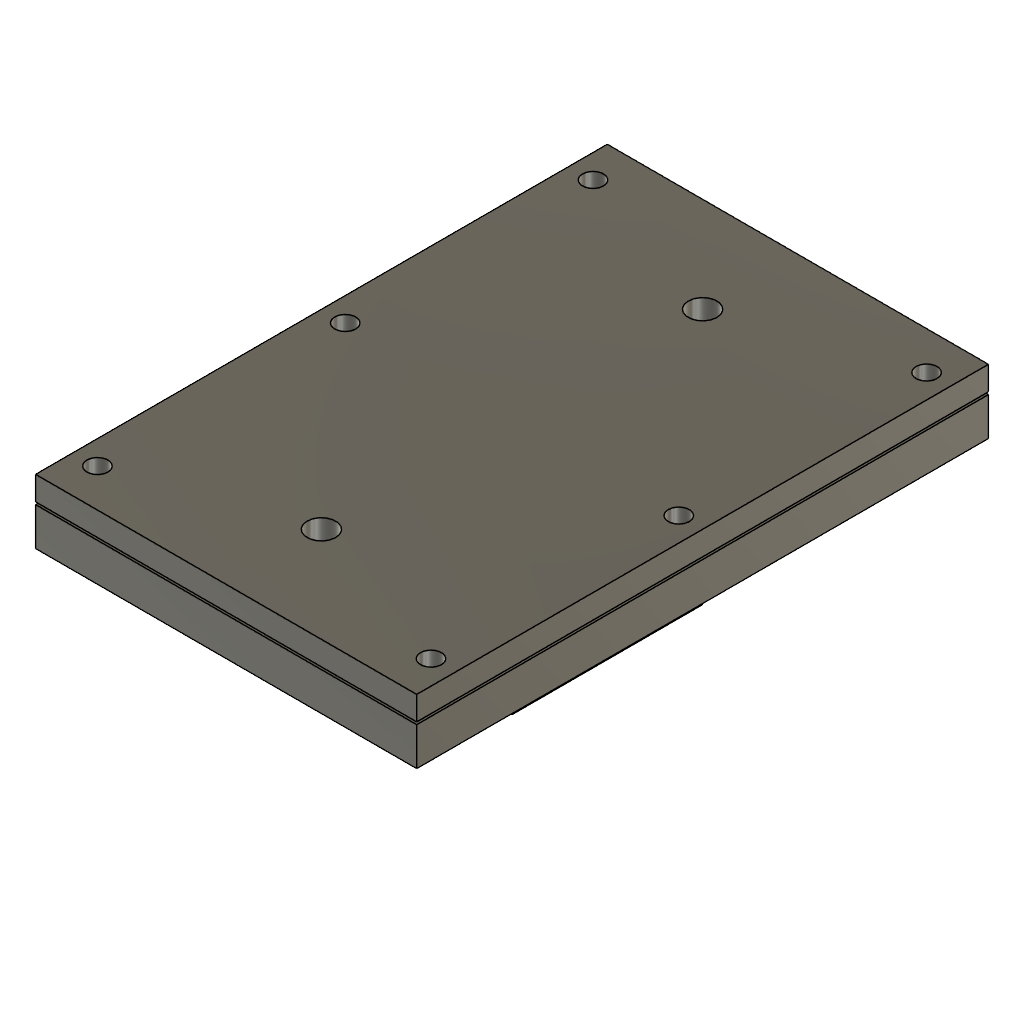
Straight_Channel_Baseline (Autodesk Fusion 360 design; units mm, degrees)
part number: 2026-11-02-01-28-26-651
part number: 2026-11-02-01-28-26-976
part number: 2026-11-02-01-28-28-252
part number: 2026-11-02-01-28-28-401
part number: 2026-11-02-01-28-28-811
part number: 2026-11-02-01-28-28-968
Autodesk Fusion 360 part; units mm, degrees
ref_plane "WorkPlane1" through (0, 0, 0) normal (0, 0, 1) x (1, 0, 0) in component "Aluminium cold plate - provisional 120 x 80 x 8 mm"
sketch "Base stock sketch" plane through (0, 0, 0) normal (0, 0, 1) x (1, 0, 0) in component "Aluminium cold plate - provisional 120 x 80 x 8 mm"
  line L0 (0, 0) -> (80, 0)
  line L1 (80, 0) -> (80, 120)
  line L2 (80, 120) -> (0, 120)
  line L3 (0, 120) -> (0, 0)
extrude "Base stock" add sketch "Base stock sketch" along normal blind 8 makes body 1 in component "Aluminium cold plate - provisional 120 x 80 x 8 mm"
ref_plane "WorkPlane2" through (0, 0, 8) normal (0, 0, 1) x (1, 0, 0) in component "Aluminium cold plate - provisional 120 x 80 x 8 mm"
sketch "16 channels - 2 wide x 3 deep sketch" plane through (0, 0, 8) normal (0, 0, 1) x (1, 0, 0) in component "Aluminium cold plate - provisional 120 x 80 x 8 mm"
  line L0 (12.75, 25) -> (14.75, 25)
  line L1 (14.75, 25) -> (14.75, 95)
  line L2 (14.75, 95) -> (12.75, 95)
  line L3 (12.75, 95) -> (12.75, 25)
  line L4 (16.25, 25) -> (18.25, 25)
  line L5 (18.25, 25) -> (18.25, 95)
  line L6 (18.25, 95) -> (16.25, 95)
  line L7 (16.25, 95) -> (16.25, 25)
  line L8 (19.75, 25) -> (21.75, 25)
  line L9 (21.75, 25) -> (21.75, 95)
  line L10 (21.75, 95) -> (19.75, 95)
  line L11 (19.75, 95) -> (19.75, 25)
  line L12 (23.25, 25) -> (25.25, 25)
  line L13 (25.25, 25) -> (25.25, 95)
  line L14 (25.25, 95) -> (23.25, 95)
  line L15 (23.25, 95) -> (23.25, 25)
  line L16 (26.75, 25) -> (28.75, 25)
  line L17 (28.75, 25) -> (28.75, 95)
  line L18 (28.75, 95) -> (26.75, 95)
  line L19 (26.75, 95) -> (26.75, 25)
  line L20 (30.25, 25) -> (32.25, 25)
  line L21 (32.25, 25) -> (32.25, 95)
  line L22 (32.25, 95) -> (30.25, 95)
  line L23 (30.25, 95) -> (30.25, 25)
  line L24 (33.75, 25) -> (35.75, 25)
  line L25 (35.75, 25) -> (35.75, 95)
  line L26 (35.75, 95) -> (33.75, 95)
  line L27 (33.75, 95) -> (33.75, 25)
  line L28 (37.25, 25) -> (39.25, 25)
  line L29 (39.25, 25) -> (39.25, 95)
  line L30 (39.25, 95) -> (37.25, 95)
  line L31 (37.25, 95) -> (37.25, 25)
  line L32 (40.75, 25) -> (42.75, 25)
  line L33 (42.75, 25) -> (42.75, 95)
  line L34 (42.75, 95) -> (40.75, 95)
  line L35 (40.75, 95) -> (40.75, 25)
  line L36 (44.25, 25) -> (46.25, 25)
  line L37 (46.25, 25) -> (46.25, 95)
  line L38 (46.25, 95) -> (44.25, 95)
  line L39 (44.25, 95) -> (44.25, 25)
  line L40 (47.75, 25) -> (49.75, 25)
  line L41 (49.75, 25) -> (49.75, 95)
  line L42 (49.75, 95) -> (47.75, 95)
  line L43 (47.75, 95) -> (47.75, 25)
  line L44 (51.25, 25) -> (53.25, 25)
  line L45 (53.25, 25) -> (53.25, 95)
  line L46 (53.25, 95) -> (51.25, 95)
  line L47 (51.25, 95) -> (51.25, 25)
  line L48 (54.75, 25) -> (56.75, 25)
  line L49 (56.75, 25) -> (56.75, 95)
  line L50 (56.75, 95) -> (54.75, 95)
  line L51 (54.75, 95) -> (54.75, 25)
  line L52 (58.25, 25) -> (60.25, 25)
  line L53 (60.25, 25) -> (60.25, 95)
  line L54 (60.25, 95) -> (58.25, 95)
  line L55 (58.25, 95) -> (58.25, 25)
  line L56 (61.75, 25) -> (63.75, 25)
  line L57 (63.75, 25) -> (63.75, 95)
  line L58 (63.75, 95) -> (61.75, 95)
  line L59 (61.75, 95) -> (61.75, 25)
  line L60 (65.25, 25) -> (67.25, 25)
  line L61 (67.25, 25) -> (67.25, 95)
  line L62 (67.25, 95) -> (65.25, 95)
  line L63 (65.25, 95) -> (65.25, 25)
extrude "16 channels - 2 wide x 3 deep" cut sketch "16 channels - 2 wide x 3 deep sketch" against normal blind 3 bodies 1 in component "Aluminium cold plate - provisional 120 x 80 x 8 mm"
ref_plane "WorkPlane3" through (0, 0, 8) normal (0, 0, 1) x (1, 0, 0) in component "Aluminium cold plate - provisional 120 x 80 x 8 mm"
sketch "Inlet and outlet distribution headers sketch" plane through (0, 0, 8) normal (0, 0, 1) x (1, 0, 0) in component "Aluminium cold plate - provisional 120 x 80 x 8 mm"
  line L0 (10, 15) -> (70, 15)
  line L1 (70, 15) -> (70, 25)
  line L2 (70, 25) -> (10, 25)
  line L3 (10, 25) -> (10, 15)
  line L4 (10, 95) -> (70, 95)
  line L5 (70, 95) -> (70, 105)
  line L6 (70, 105) -> (10, 105)
  line L7 (10, 105) -> (10, 95)
extrude "Inlet and outlet distribution headers" cut sketch "Inlet and outlet distribution headers sketch" against normal blind 3 bodies 1 in component "Aluminium cold plate - provisional 120 x 80 x 8 mm"
ref_plane "WorkPlane4" through (0, 0, 8) normal (0, 0, 1) x (1, 0, 0) in component "Aluminium cold plate - provisional 120 x 80 x 8 mm"
sketch "M4 nominal clearance through holes sketch" plane through (0, 0, 8) normal (0, 0, 1) x (1, 0, 0) in component "Aluminium cold plate - provisional 120 x 80 x 8 mm"
  circle A0 centre (5, 8) radius 2.2
  circle A1 centre (5, 60) radius 2.2
  circle A2 centre (5, 112) radius 2.2
  circle A3 centre (75, 8) radius 2.2
  circle A4 centre (75, 60) radius 2.2
  circle A5 centre (75, 112) radius 2.2
extrude "M4 nominal clearance through holes" cut sketch "M4 nominal clearance through holes sketch" against normal blind 8 bodies 1 in component "Aluminium cold plate - provisional 120 x 80 x 8 mm"
ref_plane "WorkPlane1" through (0, 0, 8) normal (0, 0, 1) x (1, 0, 0) in component "Flat gasket concept - 0.5 mm uncompressed"
sketch "Gasket blank sketch" plane through (0, 0, 8) normal (0, 0, 1) x (1, 0, 0) in component "Flat gasket concept - 0.5 mm uncompressed"
  line L0 (8, 13) -> (72, 13)
  line L1 (72, 13) -> (72, 107)
  line L2 (72, 107) -> (8, 107)
  line L3 (8, 107) -> (8, 13)
extrude "Gasket blank" add sketch "Gasket blank sketch" along normal blind 0.5 separate body makes body 2 in component "Flat gasket concept - 0.5 mm uncompressed"
ref_plane "WorkPlane2" through (0, 0, 8.5) normal (0, 0, 1) x (1, 0, 0) in component "Flat gasket concept - 0.5 mm uncompressed"
sketch "Gasket fluid aperture sketch" plane through (0, 0, 8.5) normal (0, 0, 1) x (1, 0, 0) in component "Flat gasket concept - 0.5 mm uncompressed"
  line L0 (9, 14) -> (71, 14)
  line L1 (71, 14) -> (71, 106)
  line L2 (71, 106) -> (9, 106)
  line L3 (9, 106) -> (9, 14)
extrude "Gasket fluid aperture" cut sketch "Gasket fluid aperture sketch" against normal blind 0.5 bodies 2 in component "Flat gasket concept - 0.5 mm uncompressed"
ref_plane "WorkPlane1" through (0, 0, 8.5) normal (0, 0, 1) x (1, 0, 0) in component "Aluminium cover - 5 mm - ports require fitting selection"
sketch "Cover stock sketch" plane through (0, 0, 8.5) normal (0, 0, 1) x (1, 0, 0) in component "Aluminium cover - 5 mm - ports require fitting selection"
  line L0 (0, 0) -> (80, 0)
  line L1 (80, 0) -> (80, 120)
  line L2 (80, 120) -> (0, 120)
  line L3 (0, 120) -> (0, 0)
extrude "Cover stock" add sketch "Cover stock sketch" along normal blind 5 separate body makes body 3 in component "Aluminium cover - 5 mm - ports require fitting selection"
ref_plane "WorkPlane2" through (0, 0, 13.5) normal (0, 0, 1) x (1, 0, 0) in component "Aluminium cover - 5 mm - ports require fitting selection"
sketch "Cover bolt clearance sketch" plane through (0, 0, 13.5) normal (0, 0, 1) x (1, 0, 0) in component "Aluminium cover - 5 mm - ports require fitting selection"
  circle A0 centre (5, 8) radius 2.2
  circle A1 centre (5, 60) radius 2.2
  circle A2 centre (5, 112) radius 2.2
  circle A3 centre (75, 8) radius 2.2
  circle A4 centre (75, 60) radius 2.2
  circle A5 centre (75, 112) radius 2.2
extrude "Cover bolt clearance" cut sketch "Cover bolt clearance sketch" against normal blind 5 bodies 3 in component "Aluminium cover - 5 mm - ports require fitting selection"
ref_plane "WorkPlane3" through (0, 0, 13.5) normal (0, 0, 1) x (1, 0, 0) in component "Aluminium cover - 5 mm - ports require fitting selection"
sketch "6 mm conceptual fluid bores - NOT finished threaded ports sketch" plane through (0, 0, 13.5) normal (0, 0, 1) x (1, 0, 0) in component "Aluminium cover - 5 mm - ports require fitting selection"
  circle A0 centre (40, 20) radius 3
  circle A1 centre (40, 100) radius 3
extrude "6 mm conceptual fluid bores - NOT finished threaded ports" cut sketch "6 mm conceptual fluid bores - NOT finished threaded ports sketch" against normal blind 5 bodies 3 in component "Aluminium cover - 5 mm - ports require fitting selection"
ref_plane "WorkPlane1" through (0, 0, -20.2) normal (0, 0, 1) x (1, 0, 0) in component "THYRISTOR ENVELOPE ONLY - replace with datasheet geometry"
sketch "Assumed 40 x 40 x 20 mm envelope sketch" plane through (0, 0, -20.2) normal (0, 0, 1) x (1, 0, 0) in component "THYRISTOR ENVELOPE ONLY - replace with datasheet geometry"
  line L0 (20, 40) -> (60, 40)
  line L1 (60, 40) -> (60, 80)
  line L2 (60, 80) -> (20, 80)
  line L3 (20, 80) -> (20, 40)
extrude "Assumed 40 x 40 x 20 mm envelope" add sketch "Assumed 40 x 40 x 20 mm envelope sketch" along normal blind 20 separate body makes body 4 in component "THYRISTOR ENVELOPE ONLY - replace with datasheet geometry"
ref_plane "WorkPlane1" through (0, 0, -0.2) normal (0, 0, 1) x (1, 0, 0) in component "Thermal interface envelope - selection pending"
sketch "Assumed interface envelope sketch" plane through (0, 0, -0.2) normal (0, 0, 1) x (1, 0, 0) in component "Thermal interface envelope - selection pending"
  line L0 (20, 40) -> (60, 40)
  line L1 (60, 40) -> (60, 80)
  line L2 (60, 80) -> (20, 80)
  line L3 (20, 80) -> (20, 40)
extrude "Assumed interface envelope" add sketch "Assumed interface envelope sketch" along normal blind 0.2 separate body makes body 5 in component "Thermal interface envelope - selection pending"
component "Aluminium cold plate - provisional 120 x 80 x 8 mm" placed x (1, 0, 0) y (0, 1, 0) z (0, 0, 1) at (0, 0, 0)
component "Flat gasket concept - 0.5 mm uncompressed" placed x (1, 0, 0) y (0, 1, 0) z (0, 0, 1) at (0, 0, 0)
component "Aluminium cover - 5 mm - ports require fitting selection" placed x (1, 0, 0) y (0, 1, 0) z (0, 0, 1) at (0, 0, 0)
component "THYRISTOR ENVELOPE ONLY - replace with datasheet geometry" placed x (1, 0, 0) y (0, 1, 0) z (0, 0, 1) at (0, 0, 0)
component "Thermal interface envelope - selection pending" placed x (1, 0, 0) y (0, 1, 0) z (0, 0, 1) at (0, 0, 0)
equation "d7 = -( 3 mm )"
equation "d11 = -( 3 mm )"
equation "d15 = -( 8 mm )"
equation "d23 = -( 0.5 mm )"
equation "d31 = -( 5 mm )"
equation "d35 = -( 5 mm )"
